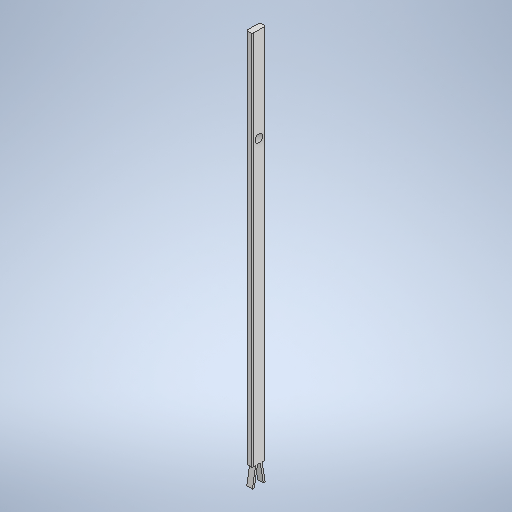
# Autodesk Inventor part: iterasi2
Saved by Autodesk Inventor 2026.2 (Build 302298010, 298A)
## iProperties
Created: 2026-11-09
Part Number: iterasi2
Material: Generic
Document SubType Name: Modeling
Designer: Acer
Density: 1 g/cm^3
Appearance: Default
Author: Acer
Autodesk Inventor part; units mm, degrees
ref_plane "YZ Plane" through (0, 0, 0) normal (1, 0, 0) x (0, 1, 0)
ref_plane "XZ Plane" through (0, 0, 0) normal (0, 1, 0) x (-1, 0, 0)
ref_plane "XY Plane" through (0, 0, 0) normal (0, 0, 1) x (1, 0, 0)
sketch "Sketch2" plane through (0, 0, 0) normal (1, 0, 0) x (0, 1, 0)
  line L0 (-200, 0) -> (200, 0)
  line L1 (200, -7) -> (200, 7)
  line L2 (200, 7) -> (-200, 7)
  line L3 (-200, -7) -> (200, -7)
  line L4 (200, -7) -> (200, 7)
  line L5 (200, 0) -> (100, 0)
  circle A0 centre (100, 0) radius 4.25
  line L6 (-200, 0) -> (-220, 0)
  line L7 (-200, -1.5) -> (-200, 1.5)
  line L8 (-200, 3.5) -> (-220, 6.7689)
  line L9 (-220, 6.7689) -> (-220, 4.7689)
  line L10 (-200, 1.5) -> (-220, 4.7689)
  line L11 (-200, -3.5) -> (-220, -6.7689)
  line L12 (-220, -6.7689) -> (-220, -4.7689)
  line L13 (-200, -1.5) -> (-220, -4.7689)
  line L14 (-200, 7) -> (-200, 3.5)
  line L15 (-200, 1.5) -> (-200, -1.5)
  line L16 (-200, -3.5) -> (-200, -7)
  point P0 (0, 0)
  dimension "d4" = 400
  dimension "d6" = 14
  dimension "d7" = 14
  dimension "d8" = 100
  dimension "d9" = 8.5
  dimension "d10" = 20
  dimension "d11" = 7
  dimension "d12" = 2
  dimension "d13" = 2
  constraints: 34 end point, 4 parallel, 3 midpoint, 3 perpendicular, 3 symmetric about line, 2 horizontal, 2 point on line, 2 vertical, 1 centre point, 1 coincident
  measures "d4" distance of L0.start L0.end
  measures "d6" distance of L1.start L1.end
  measures "d7" distance of L3.start L2.end
  measures "d8" distance of L0.end L5.end
  measures "d9" diameter of A0
  measures "d10" distance of L0.start L6.end
  measures "d11" distance of L11.start L8.start
  measures "d12" distance of L8.end L9.end
  measures "d13" distance of L7.end L8.start
extrude "Extrusion1" add sketch "Sketch2" along normal blind 6 contours A0 L0 L7 L10 L9 L8 L14 L2 L1 | L0 L1 L3 L16 L11 L12 L13 L7 A0
fillet "Fillet1" radius 1 1 edges at (6, 0, 7)
fillet "Fillet2" radius 1 3 edges at (6, 0, -7) (0, 0, 7) (0, 0, -7)
body "Solid1"
